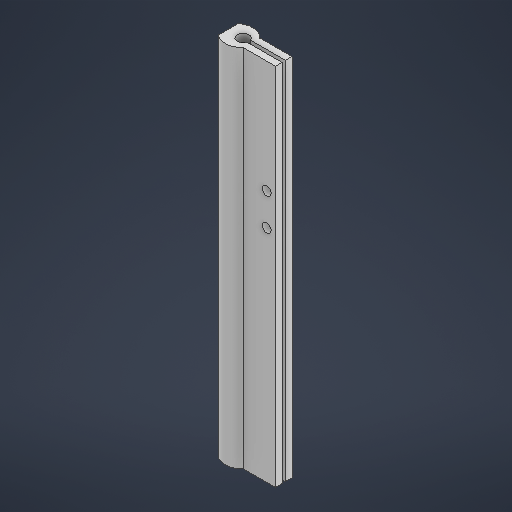
# Autodesk Inventor part: support_nageoire
Saved by Autodesk Inventor 2026.1 (Build 301233020, 233B)
## iProperties
Created: 2026-10-28
Part Number: support_nageoire
Material: Generic
Document SubType Name: Modeling
Designer: matar
Density: 1 g/cm^3
Appearance: Default
Author: matar
Autodesk Inventor part; units mm, degrees
ref_plane "YZ Plane" through (0, 0, 0) normal (1, 0, 0) x (0, 1, 0)
ref_plane "XZ Plane" through (0, 0, 0) normal (0, 1, 0) x (-1, 0, 0)
ref_plane "XY Plane" through (0, 0, 0) normal (0, 0, 1) x (1, 0, 0)
sketch "Sketch1" plane through (0, 0, 0) normal (0, 1, 0) x (-1, 0, 0)
  line L0 (11, 0) -> (0, 0)
  line L1 (0, 0) -> (0, -2.25)
  line L2 (0, -2.25) -> (12, -2.25)
  line L3 (0.0315, -3.45) -> (12.0315, -3.45)
  line L4 (0.0315, -3.45) -> (0.0315, -5.7)
  line L5 (0.0315, -5.7) -> (11.0315, -5.7)
  arc A0 (12.0315, -3.45) -> (12, -2.25) centre (13.9229, -2.8) ccw
  line L6 (19.0315, 0.65) -> (19.0315, -6.35)
  arc A1 (11.0315, -5.7) -> (19.0315, -6.35) centre (15.3927, -1.5793) ccw
  arc A2 (19.0315, 0.65) -> (11, 0) centre (15.3744, -4.1067) ccw
  dimension "d0" = 11
  dimension "d1" = 11
  dimension "d2" = 12
  dimension "d3" = 12
  dimension "d4" = 2.25
  dimension "d5" = 2.25
  dimension "d6" = 1.2
  dimension "d7" = 7
  dimension "d8" = 2
  dimension "d9" = 19
  dimension "d12" = 6
  dimension "d13" = 0.65
  dimension "d14" = 0.65
  dimension "d16" = 6
  constraints: 14 end point, 6 point on circle, 3 centre point, 3 perpendicular, 2 horizontal, 2 vertical
  measures "d0" distance of L0.start L0.end
  measures "d1" distance of L4.end L5.end
  measures "d2" distance of L1.end L2.end
  measures "d3" distance of L3.start L3.end
  measures "d4" distance of L0.end L1.end
  measures "d5" distance of L3.start L4.end
  measures "d6" distance between parallel lines of L3 L2
  measures "d7" distance of L6.start L6.end
  measures "d8" radius of A0
  measures "d9" distance between parallel lines of L4 L6
  measures "d12" radius of A1
  measures "d13" vertical distance of L6.start L0.start
  measures "d14" vertical distance of L6.end L5.end
  measures "d16" radius of A2
extrude "Extrusion1" add sketch "Sketch1" along normal blind 125
sketch "Sketch2" plane through (-11, 0, 0) normal (0, 0, 1) x (1, 0, 0)
  circle A0 centre (8, 86.5) radius 1.55
  circle A1 centre (8, 75.5) radius 1.55
  line L0 (0, 0) -> (0, 125) projected
  line L1 (0, 125) -> (11, 125) projected
  point P0 (11, 0)
  dimension "d19" = 3.1
  dimension "d20" = 3.1
  dimension "d21" = 11
  dimension "d22" = 8
  dimension "d23" = 8
  dimension "d24" = 38.5
  constraints: 2 centre point
  measures "d19" diameter of A0
  measures "d20" diameter of A1
  measures "d21" distance of A1.centre A0.centre
  measures "d22" distance from line of A0.centre L0
  measures "d23" distance from line of A1.centre L0
  measures "d24" distance from line of L1 A0.centre
extrude "Extrusion2" cut sketch "Sketch2" against normal through all
body "Solid1"
